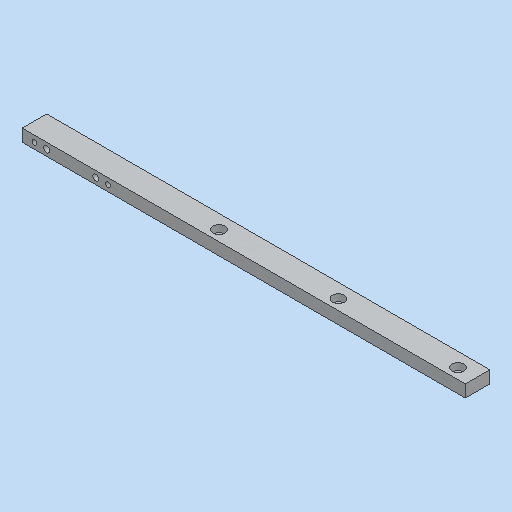
# Autodesk Inventor part: MM0948AN100_G01_104
Saved by Autodesk Inventor 2023.3 (Build 273359000, 359)
## iProperties
Part Number: MM0948AN100_G01_104
Material: 3.3547 AlMg4,5Mn0,7 - AW 5083
Description: =<RBPARTNOTITLE2>
Document SubType Name: Modeling
Designer: ric7an
Mass: 187.186 g
Surface Area: 237.231 cm^2
Volume: 69.3282 cm^3
Density: 2.7 g/cm^3
Appearance: Aluminium AnP
Created: 2023-03-23
RBDOCUMENTTYPE: DRF
RBDOCUMENTVERSION: 00
RBDRAWINGMAINSCALE: 1:1
RBDRAWINGMISSINGSPEC: --
RBDRAWINGVOLUME: --
RBGBEDGESIN1: +0,5
RBGBEDGESIN2: +0,2
RBGBEDGESOUT1: -0,3
RBGBEDGESOUT2: -0,1
RBMATERIAL: =<Material>
RBMATMEETS: --
RBMATNO: =<Part Number>
RBPARTMADEOF: 10 x 20 x 361,5 (FM)
RBPARTNO: SIEHE MNR
RBPARTNOTITLE1: manufactured part
RBPARTNOTITLE2: Anfertigungsteil
RBPARTSAFETYINDICATOR: --
RBSURFACE: anodised colourless
RBSURFACE2: eloxiert farblos
RBZEDGESNORM: ISO13715:2002-06
RBZGENDIMCLASS: m
RBZGENDIMNORM: ISO 2768-1:1989-11
RBZGENGEOCLASS: H
RBZGENGEONORM: ISO 2768-2:1989-11
RBZSURFACENORM: ISO13D2:2002-02
RBZTOLERANCENORM: ISO 14405-1:2010-12
AnP_Material: =<Material>
AnP_TemplVers: 20190222
AnP_Kategorie: 1
MaxAbmaße: 10 x 20 x 361,5 (FM)
AnP_Kommentar_aktuell: =<Comments>
AnP_Material_aktuell: =<Material>
Author: FH/Wi
Keywords: =<RBPARTMADEOF>
Comments: =<RBSURFACE2>
Revision Number: 01
Autodesk Inventor part; units mm, degrees
ref_plane "YZ Plane" through (0, 0, 0) normal (1, 0, 0) x (0, 1, 0)
ref_plane "XZ Plane" through (0, 0, 0) normal (0, 1, 0) x (-1, 0, 0)
ref_plane "XY Plane" through (0, 0, 0) normal (0, 0, 1) x (1, 0, 0)
sketch "Skizze1" plane through (0, 0, 0) normal (0, 0, 1) x (1, 0, 0)
  line L0 (-180.75, 0) -> (180.75, 0)
  line L1 (180.75, 0) -> (180.75, 20)
  line L2 (180.75, 20) -> (-180.75, 20)
  line L3 (-180.75, 20) -> (-180.75, 0)
  line L4 (0, 24) -> (0, -4) projected
  line L5 (-253.05, 0) -> (253.05, 0) projected
  point P0 (0, 0)
  dimension "d0" = 20
  dimension "d1" = 361.5
  constraints: 8 end point, 2 parallel, 1 collinear, 1 horizontal, 1 perpendicular, 1 other
  measures "d0" distance of L0.end L1.end
  measures "d1" distance of L1.end L2.end
extrude "Extrusion1" add sketch "Skizze1" along normal blind 10
sketch "Skizze7" plane through (0, 0, 10) normal (0, 0, 1) x (1, 0, 0)
  line L0 (180.75, 20) -> (-180.75, 20) projected
  line L1 (0, 24) -> (0, -4) projected
  line L2 (-261.1, 0) -> (261.1, 0) projected
  line L3 (180.75, 0) -> (180.75, 20) projected
  line L4 (-180.75, 20) -> (-180.75, 0) projected
  point P0 (0, 0)
  point P1 (-28.75, 8.5)
  point P2 (166.25, 8.5)
  point P3 (68.75, 8.5)
  dimension "d33" = 195
  dimension "d34" = 11.5
  dimension "d53" = 97.5
  dimension "d65" = 14.5
  constraints: 2 horizontal alignment
  measures "d33" distance of point (166.25, 8.5) point (-28.75, 8.5)
  measures "d34" distance from line of L0 point (166.25, 8.5)
  measures "d53" distance of point (166.25, 8.5) point (68.75, 8.5)
  measures "d65" distance from line of L3 point (166.25, 8.5)
hole "Bohrung3" at (-28.75, 8.5, 10) at (166.25, 8.5, 10) at (68.75, 8.5, 10) direction (0, 0, -1) diameter 5.5 end through all counterbore diameter 10 counterbore depth 5.7 clearance for "Inbusschraube ISO 4762  versenkt" size "M5" standard "ISO"
sketch "Skizze8" plane through (-180.75, 20, 0) normal (0, 1, 0) x (1, 0, 0)
  line L0 (0, 0) -> (0, -10) projected
  line L1 (361.5, -10) -> (0, -10) projected
  point P0 (180.75, 0)
  point P1 (10, -5)
  point P2 (70, -5)
  dimension "d43" = 60
  dimension "d44" = 10
  dimension "d45" = 5
  constraints: 1 horizontal alignment
  measures "d43" distance of point (70, -5) point (10, -5)
  measures "d44" distance from line of L0 point (10, -5)
  measures "d45" distance from line of L1 point (10, -5)
hole "Bohrung4" at (-170.75, 20, 5) at (-110.75, 20, 5) direction (0, -1, 0) diameter 4.134 end through all thread size "M5x0.8" designation "M5" class "6H" standard "ISO Metric profile"
sketch "Skizze9" plane through (-180.75, 0, 0) normal (0, -1, 0) x (1, 0, 0)
  circle A0 centre (10, 5) radius 2.067 projected
  line L0 (0, 0) -> (0, 10) projected
  line L1 (361.5, 0) -> (361.5, 10) projected
  circle A1 centre (70, 5) radius 2.067 projected
  point P0 (180.75, 0)
  point P1 (20, 5)
  point P2 (60, 5)
  dimension "d66" = 10
  dimension "d67" = 10
  constraints: 2 horizontal alignment
  measures "d66" distance of point (20, 5) A0.centre
  measures "d67" distance of A1.centre point (60, 5)
hole "Bohrung5" at (-160.75, 0, 5) at (-120.75, 0, 5) direction (0, 1, 0) diameter 5 end through all
